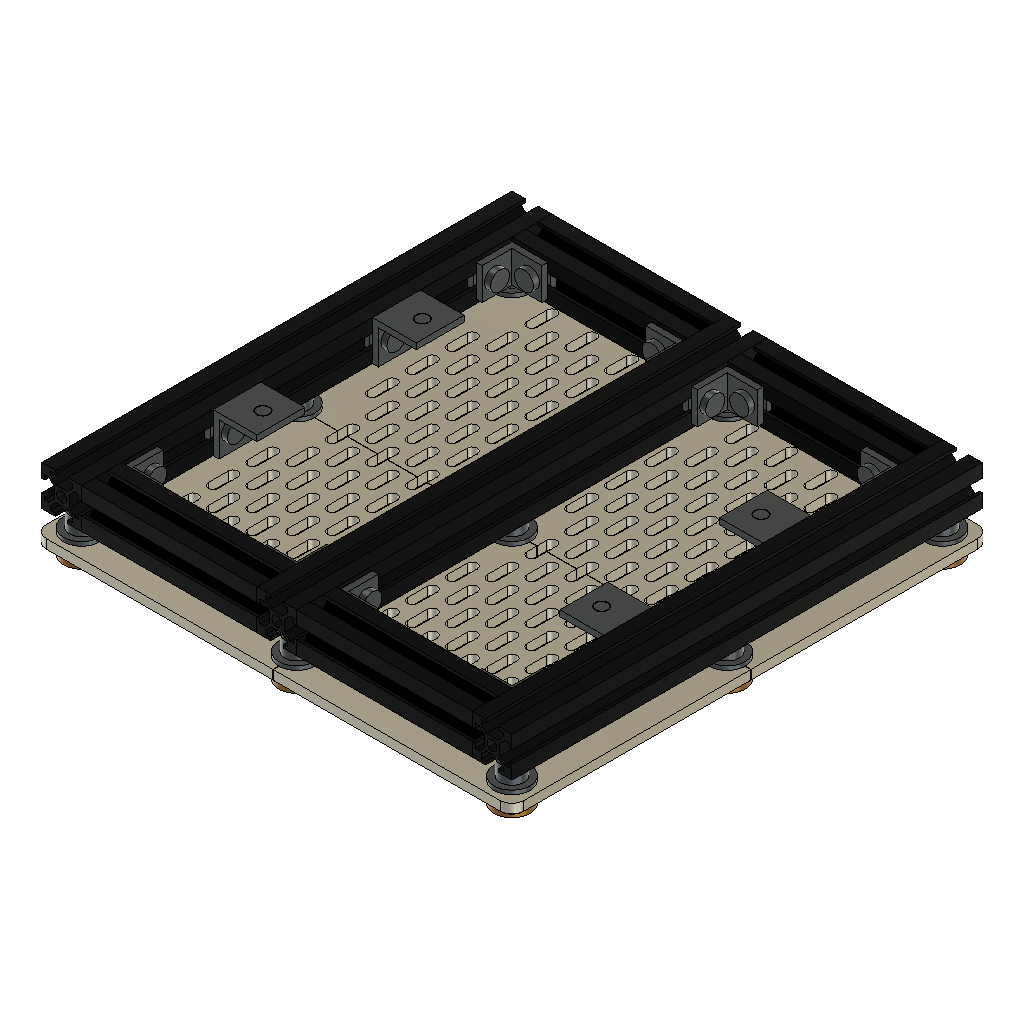
frame-assembly-v03 (Autodesk Fusion 360 design; units mm, degrees)
part number: 2026-10-27-16-26-25-331
part number: 2026-10-27-16-26-25-834
part number: 2026-10-27-16-26-31-002
part number: 2026-10-27-16-26-43-557
part number: 2026-10-27-16-27-03-703
part number: 2026-10-27-16-31-45-844
part number: 2026-10-27-16-32-06-116
part number: 2026-10-27-16-32-29-126
part number: 2026-10-27-16-32-54-655
part number: 2026-10-27-16-33-23-056
part number: 2026-10-27-16-33-54-185
part number: 2026-10-27-16-34-28-220
part number: 2026-10-27-16-50-17-475
part number: 2026-10-27-16-50-20-825
part number: 2026-10-27-16-50-30-983
part number: 2026-10-27-16-50-35-846
part number: 2026-10-27-16-50-39-540
part number: 2026-10-27-16-50-48-951
part number: 2026-10-27-16-50-52-817
part number: 2026-10-27-16-51-04-303
part number: 2026-10-27-16-51-09-754
part number: 2026-10-27-16-51-14-010
part number: 2026-10-27-16-51-20-182
part number: 2026-10-27-16-51-24-601
part number: 2026-10-27-16-51-37-683
part number: 2026-10-27-16-51-43-962
part number: 2026-10-27-16-51-48-789
part number: 2026-10-27-16-51-55-690
part number: 2026-10-27-16-52-00-678
part number: 2026-10-27-16-52-15-396
part number: 2026-10-27-16-52-22-451
part number: 2026-10-27-16-52-27-802
part number: 2026-10-27-16-52-35-541
part number: 2026-10-27-16-52-41-572
part number: 2026-10-27-16-52-57-940
part number: 2026-10-27-16-53-05-661
part number: 2026-10-27-16-53-11-607
part number: 2026-10-27-16-53-30-566
part number: 2026-10-27-16-53-36-573
part number: 2026-10-27-16-53-54-171
part number: 2026-10-27-16-54-02-574
part number: 2026-10-27-16-54-08-987
part number: 2026-10-27-16-54-18-294
part number: 2026-10-27-16-54-24-887
part number: 2026-10-27-16-54-44-208
part number: 2026-10-27-16-54-53-574
part number: 2026-10-27-16-55-00-850
part number: 2026-10-27-16-55-11-193
part number: 2026-10-27-16-55-18-638
part number: 2026-10-27-16-55-40-176
part number: 2026-10-27-16-55-50-211
part number: 2026-10-27-16-55-57-944
part number: 2026-10-27-16-56-09-225
part number: 2026-10-27-16-56-17-698
part number: 2026-10-27-16-56-42-856
part number: 2026-10-27-16-56-54-020
part number: 2026-10-27-16-57-02-669
part number: 2026-10-27-16-57-38-922
part number: 2026-10-27-16-58-05-764
part number: 2026-10-27-16-58-18-225
part number: 2026-10-27-16-58-32-485
part number: 2026-10-27-16-58-45-089
part number: 2026-10-27-16-59-01-629
part number: 2026-10-27-16-59-30-085
part number: 2026-10-27-16-59-42-842
part number: 2026-10-27-16-59-57-737
part number: 2026-10-27-17-00-10-688
part number: 2026-10-27-17-00-34-215
part number: 2026-10-27-17-01-04-234
part number: 2026-10-27-17-01-17-714
part number: 2026-10-27-17-01-33-549
part number: 2026-10-27-17-01-47-217
part number: 2026-10-27-17-02-03-116
part number: 2026-10-27-17-02-34-830
part number: 2026-10-27-17-02-49-172
part number: 2026-10-27-17-03-05-831
part number: 2026-10-27-17-03-20-448
part number: 2026-10-27-17-04-26-782
part number: 2026-10-27-17-05-00-628
part number: 2026-10-27-17-05-15-608
part number: 2026-10-27-17-05-33-129
part number: 2026-10-27-17-05-48-959
part number: 2026-10-27-17-06-06-857
part number: 2026-10-27-17-06-42-303
part number: 2026-10-27-17-06-58-375
part number: 2026-10-27-17-07-16-885
part number: 2026-10-27-17-07-33-101
part number: 2026-10-27-17-07-52-230
part number: 2026-10-27-17-08-29-249
part number: 2026-10-27-17-08-46-003
part number: 2026-10-27-17-09-05-462
part number: 2026-10-27-17-09-22-396
part number: 2026-10-27-17-09-42-184
part number: 2026-10-27-17-10-21-471
part number: 2026-10-27-17-10-38-969
part number: 2026-10-27-17-10-59-407
part number: 2026-10-27-17-11-17-340
part number: 2026-10-27-17-11-39-314
part number: 2026-10-27-17-12-12-457
part number: 2026-10-27-17-12-31-147
part number: 2026-10-27-17-13-02-003
part number: 2026-10-27-17-13-21-406
part number: 2026-10-27-17-13-50-114
part number: 2026-10-27-17-14-04-208
part number: 2026-10-27-17-14-39-027
part number: 2026-10-27-17-14-58-920
part number: 2026-10-27-17-15-33-071
part number: 2026-10-27-17-15-53-097
part number: 2026-10-27-17-16-23-156
part number: 2026-10-27-17-16-38-033
part number: 2026-10-27-17-17-14-342
part number: 2026-10-27-17-17-34-865
part number: 2026-10-27-17-18-08-534
part number: 2026-10-27-17-18-29-482
part number: 2026-10-27-17-19-04-183
part number: 2026-10-27-17-19-22-590
part number: 2026-10-27-17-20-03-829
part number: 2026-10-27-17-20-26-353
part number: 2026-10-27-17-21-03-350
part number: 2026-10-27-17-21-26-206
part number: 2026-10-27-17-22-00-497
Autodesk Fusion 360 part; units mm, degrees
(part 1 of 10)
sketch "01 Panel blank sketch" plane through (0, 0, 0) normal (0, 0, 1) x (1, 0, 0) in component "Panel lower left"
  line L0 (0.1, 0.1) -> (119.9, 0.1)
  line L1 (119.9, 0.1) -> (119.9, 119.9)
  line L2 (119.9, 119.9) -> (0.1, 119.9)
  line L3 (0.1, 119.9) -> (0.1, 0.1)
  dimension "d57" = 0.1
  dimension "d58" = 0.1
  dimension "d59" = 119.8
  dimension "d60" = 119.8
  constraint horizontal L0
  constraint vertical L1
  constraint horizontal L2
  constraint vertical L3
  measures "d57" horizontal distance of origin L0.start
  measures "d58" vertical distance of origin L0.start
  measures "d59" horizontal distance of L0.start L0.end
  measures "d60" vertical distance of L0.end L1.end
extrude "01 Panel blank" add sketch "01 Panel blank sketch" along normal blind 5 makes body 1 in component "Panel lower left"
fillet "02 Rounded exterior corners" radius 6 1 edges at (0.1, 0.1, 2.5) on bodies 1 in component "Panel lower left"
sketch "03 A main constrained seed" plane through (0, 0, 0) normal (0, 0, 1) x (1, 0, 0) in component "Panel lower left"
  line L0 (47.5, 25) -> (47.5, 35)
  arc A0 (47.5, 35) -> (42.5, 35) centre (45, 35) ccw
  line L1 (42.5, 35) -> (42.5, 25)
  arc A1 (42.5, 25) -> (47.5, 25) centre (45, 25) ccw
  line L2 (45, 25) -> (45, 35) construction
  line L3 (45, 25) -> (55, 25) construction
  dimension "d65" = 5
  dimension "d66" = 10
  dimension "d67" = 90
  dimension "d68" = 10
  dimension "d69" = 45
  dimension "d70" = 25
  constraint tangent L0 A0
  constraint tangent A0 L1
  constraint tangent L1 A1
  constraint tangent L0 A1
  constraint parallel L0 L1
  constraint horizontal L3
  measures "d65" diameter of A0
  measures "d66" distance of A1.centre A0.centre
  measures "d67" angle of L2 L3
  measures "d68" horizontal distance of A1.centre L3.end
  measures "d69" horizontal distance of origin A1.centre
  measures "d70" vertical distance of origin A1.centre
extrude "03 A main through cut" cut sketch "03 A main constrained seed" along normal blind 5 bodies 1 in component "Panel lower left"
pattern_linear "03 A main lattice" count 4 spacing 20 along (1, 0, 0) count 5 spacing 20 along (0, 1, 0) of "03 A main through cut" in component "Panel lower left"
sketch "04 A end strip constrained seed" plane through (0, 0, 0) normal (0, 0, 1) x (1, 0, 0) in component "Panel lower left"
  line L0 (27.5, 45) -> (27.5, 55)
  arc A0 (27.5, 55) -> (22.5, 55) centre (25, 55) ccw
  line L1 (22.5, 55) -> (22.5, 45)
  arc A1 (22.5, 45) -> (27.5, 45) centre (25, 45) ccw
  line L2 (25, 45) -> (25, 55) construction
  line L3 (25, 45) -> (35, 45) construction
  dimension "d77" = 5
  dimension "d78" = 10
  dimension "d79" = 90
  dimension "d80" = 10
  dimension "d81" = 25
  dimension "d82" = 45
  constraint tangent L0 A0
  constraint tangent A0 L1
  constraint tangent L1 A1
  constraint tangent L0 A1
  constraint parallel L0 L1
  constraint horizontal L3
  measures "d77" diameter of A0
  measures "d78" distance of A1.centre A0.centre
  measures "d79" angle of L2 L3
  measures "d80" horizontal distance of A1.centre L3.end
  measures "d81" horizontal distance of origin A1.centre
  measures "d82" vertical distance of origin A1.centre
extrude "04 A end strip through cut" cut sketch "04 A end strip constrained seed" along normal blind 5 bodies 1 in component "Panel lower left"
pattern_linear "04 A end strip lattice" count 1 spacing 20 along (1, 0, 0) count 3 spacing 20 along (0, 1, 0) of "04 A end strip through cut" in component "Panel lower left"
sketch "05 B main constrained seed" plane through (0, 0, 0) normal (0, 0, 1) x (1, 0, 0) in component "Panel lower left"
  line L0 (37.5, 15) -> (37.5, 25)
  arc A0 (37.5, 25) -> (32.5, 25) centre (35, 25) ccw
  line L1 (32.5, 25) -> (32.5, 15)
  arc A1 (32.5, 15) -> (37.5, 15) centre (35, 15) ccw
  line L2 (35, 15) -> (35, 25) construction
  line L3 (35, 15) -> (45, 15) construction
  dimension "d89" = 5
  dimension "d90" = 10
  dimension "d91" = 90
  dimension "d92" = 10
  dimension "d93" = 35
  dimension "d94" = 15
  constraint tangent L0 A0
  constraint tangent A0 L1
  constraint tangent L1 A1
  constraint tangent L0 A1
  constraint parallel L0 L1
  constraint horizontal L3
  measures "d89" diameter of A0
  measures "d90" distance of A1.centre A0.centre
  measures "d91" angle of L2 L3
  measures "d92" horizontal distance of A1.centre L3.end
  measures "d93" horizontal distance of origin A1.centre
  measures "d94" vertical distance of origin A1.centre
extrude "05 B main through cut" cut sketch "05 B main constrained seed" along normal blind 5 bodies 1 in component "Panel lower left"
pattern_linear "05 B main lattice" count 4 spacing 20 along (1, 0, 0) count 6 spacing 20 along (0, 1, 0) of "05 B main through cut" in component "Panel lower left"
sketch "06 B end strip constrained seed" plane through (0, 0, 0) normal (0, 0, 1) x (1, 0, 0) in component "Panel lower left"
  line L0 (117.5, 35) -> (117.5, 45)
  arc A0 (117.5, 45) -> (112.5, 45) centre (115, 45) ccw
  line L1 (112.5, 45) -> (112.5, 35)
  arc A1 (112.5, 35) -> (117.5, 35) centre (115, 35) ccw
  line L2 (115, 35) -> (115, 45) construction
  line L3 (115, 35) -> (125, 35) construction
  dimension "d101" = 5
  dimension "d102" = 10
  dimension "d103" = 90
  dimension "d104" = 10
  dimension "d105" = 115
  dimension "d106" = 35
  constraint tangent L0 A0
  constraint tangent A0 L1
  constraint tangent L1 A1
  constraint tangent L0 A1
  constraint parallel L0 L1
  constraint horizontal L3
  measures "d101" diameter of A0
  measures "d102" distance of A1.centre A0.centre
  measures "d103" angle of L2 L3
  measures "d104" horizontal distance of A1.centre L3.end
  measures "d105" horizontal distance of origin A1.centre
  measures "d106" vertical distance of origin A1.centre
extrude "06 B end strip through cut" cut sketch "06 B end strip constrained seed" along normal blind 5 bodies 1 in component "Panel lower left"
pattern_linear "06 B end strip lattice" count 1 spacing 20 along (1, 0, 0) count 4 spacing 20 along (0, 1, 0) of "06 B end strip through cut" in component "Panel lower left"
sketch "07 Shared node clearance sketch" plane through (0, 0, 0) normal (0, 0, 1) x (1, 0, 0) in component "Panel lower left"
  circle A0 centre (12, 12) radius 4.2
  dimension "d113" = 12
  dimension "d114" = 12
  dimension "d115" = 8.4
  measures "d113" horizontal distance of origin A0.centre
  measures "d114" vertical distance of origin A0.centre
  measures "d115" diameter of A0
extrude "07 Shared node clearance" cut sketch "07 Shared node clearance sketch" along normal blind 5 bodies 1 in component "Panel lower left"
sketch "07 Shared node clearance sketch (1)" plane through (0, 0, 0) normal (0, 0, 1) x (1, 0, 0) in component "Panel lower left"
  circle A0 centre (12, 120) radius 4.2
  dimension "d118" = 12
  dimension "d119" = 120
  dimension "d120" = 8.4
  measures "d118" horizontal distance of origin A0.centre
  measures "d119" vertical distance of origin A0.centre
  measures "d120" diameter of A0
extrude "07 Shared node clearance (1)" cut sketch "07 Shared node clearance sketch (1)" along normal blind 5 bodies 1 in component "Panel lower left"
sketch "07 Shared node clearance sketch (2)" plane through (0, 0, 0) normal (0, 0, 1) x (1, 0, 0) in component "Panel lower left"
  circle A0 centre (120, 12) radius 4.2
  dimension "d123" = 120
  dimension "d124" = 12
  dimension "d125" = 8.4
  measures "d123" horizontal distance of origin A0.centre
  measures "d124" vertical distance of origin A0.centre
  measures "d125" diameter of A0
extrude "07 Shared node clearance (2)" cut sketch "07 Shared node clearance sketch (2)" along normal blind 5 bodies 1 in component "Panel lower left"
sketch "07 Shared node clearance sketch (3)" plane through (0, 0, 0) normal (0, 0, 1) x (1, 0, 0) in component "Panel lower left"
  circle A0 centre (120, 120) radius 4.2
  dimension "d128" = 120
  dimension "d129" = 120
  dimension "d130" = 8.4
  measures "d128" horizontal distance of origin A0.centre
  measures "d129" vertical distance of origin A0.centre
  measures "d130" diameter of A0
extrude "07 Shared node clearance (3)" cut sketch "07 Shared node clearance sketch (3)" along normal blind 5 bodies 1 in component "Panel lower left"
fillet "08 Rounded slot entrances and face edges" radius 0.4 2 faces at (7.5667, 63.6667, 0) (7.5667, 63.6667, 0) on bodies 1 in component "Panel lower left"
ref_plane "WorkPlane1" through (0, 0, 5) normal (0, 0, 1) x (1, 0, 0) in component "Panel lower left"
sketch "09 Blind rear key socket sketch" plane through (0, 0, 5) normal (0, 0, 1) x (1, 0, 0) in component "Panel lower left"
  circle A0 centre (115, 70) radius 1.7
  dimension "d137" = 115
  dimension "d138" = 70
  dimension "d139" = 3.4
  measures "d137" horizontal distance of origin A0.centre
  measures "d138" vertical distance of origin A0.centre
  measures "d139" diameter of A0
ref_plane "WorkPlane2" through (0, 0, 5) normal (0, 0, 1) x (1, 0, 0) in component "Panel lower left"
sketch "09 Blind rear key socket sketch (1)" plane through (0, 0, 5) normal (0, 0, 1) x (1, 0, 0) in component "Panel lower left"
  circle A0 centre (70, 115) radius 1.7
  dimension "d144" = 70
  dimension "d145" = 115
  dimension "d146" = 3.4
  measures "d144" horizontal distance of origin A0.centre
  measures "d145" vertical distance of origin A0.centre
  measures "d146" diameter of A0
ref_plane "WorkPlane3" through (0, 0, 5) normal (0, 0, 1) x (1, 0, 0) in component "Panel lower left"
sketch "10 Node register socket sketch" plane through (0, 0, 5) normal (0, 0, 1) x (1, 0, 0) in component "Panel lower left"
  circle A0 centre (7, 7) radius 1.2
  dimension "d151" = 7
  dimension "d152" = 7
  dimension "d153" = 2.4
  measures "d151" horizontal distance of origin A0.centre
  measures "d152" vertical distance of origin A0.centre
  measures "d153" diameter of A0
extrude "10 Node register socket" cut sketch "10 Node register socket sketch" against normal blind 1 bodies 1 in component "Panel lower left"
ref_plane "WorkPlane4" through (0, 0, 5) normal (0, 0, 1) x (1, 0, 0) in component "Panel lower left"
sketch "10 Node register socket sketch (1)" plane through (0, 0, 5) normal (0, 0, 1) x (1, 0, 0) in component "Panel lower left"
  circle A0 centre (7, 17) radius 1.2
  dimension "d158" = 7
  dimension "d159" = 17
  dimension "d160" = 2.4
  measures "d158" horizontal distance of origin A0.centre
  measures "d159" vertical distance of origin A0.centre
  measures "d160" diameter of A0
extrude "10 Node register socket (1)" cut sketch "10 Node register socket sketch (1)" against normal blind 1 bodies 1 in component "Panel lower left"
ref_plane "WorkPlane5" through (0, 0, 5) normal (0, 0, 1) x (1, 0, 0) in component "Panel lower left"
sketch "10 Node register socket sketch (2)" plane through (0, 0, 5) normal (0, 0, 1) x (1, 0, 0) in component "Panel lower left"
  circle A0 centre (17, 7) radius 1.2
  dimension "d165" = 17
  dimension "d166" = 7
  dimension "d167" = 2.4
  measures "d165" horizontal distance of origin A0.centre
  measures "d166" vertical distance of origin A0.centre
  measures "d167" diameter of A0
extrude "10 Node register socket (2)" cut sketch "10 Node register socket sketch (2)" against normal blind 1 bodies 1 in component "Panel lower left"
ref_plane "WorkPlane6" through (0, 0, 5) normal (0, 0, 1) x (1, 0, 0) in component "Panel lower left"
sketch "10 Node register socket sketch (3)" plane through (0, 0, 5) normal (0, 0, 1) x (1, 0, 0) in component "Panel lower left"
  circle A0 centre (17, 17) radius 1.2
  dimension "d172" = 17
  dimension "d173" = 17
  dimension "d174" = 2.4
  measures "d172" horizontal distance of origin A0.centre
  measures "d173" vertical distance of origin A0.centre
  measures "d174" diameter of A0
extrude "10 Node register socket (3)" cut sketch "10 Node register socket sketch (3)" against normal blind 1 bodies 1 in component "Panel lower left"
ref_plane "WorkPlane7" through (0, 0, 5) normal (0, 0, 1) x (1, 0, 0) in component "Panel lower left"
sketch "10 Node register socket sketch (4)" plane through (0, 0, 5) normal (0, 0, 1) x (1, 0, 0) in component "Panel lower left"
  circle A0 centre (7, 115) radius 1.2
  dimension "d179" = 7
  dimension "d180" = 115
  dimension "d181" = 2.4
  measures "d179" horizontal distance of origin A0.centre
  measures "d180" vertical distance of origin A0.centre
  measures "d181" diameter of A0
extrude "10 Node register socket (4)" cut sketch "10 Node register socket sketch (4)" against normal blind 1 bodies 1 in component "Panel lower left"
ref_plane "WorkPlane8" through (0, 0, 5) normal (0, 0, 1) x (1, 0, 0) in component "Panel lower left"
sketch "10 Node register socket sketch (5)" plane through (0, 0, 5) normal (0, 0, 1) x (1, 0, 0) in component "Panel lower left"
  circle A0 centre (17, 115) radius 1.2
  dimension "d186" = 17
  dimension "d187" = 115
  dimension "d188" = 2.4
  measures "d186" horizontal distance of origin A0.centre
  measures "d187" vertical distance of origin A0.centre
  measures "d188" diameter of A0
extrude "10 Node register socket (5)" cut sketch "10 Node register socket sketch (5)" against normal blind 1 bodies 1 in component "Panel lower left"
ref_plane "WorkPlane9" through (0, 0, 5) normal (0, 0, 1) x (1, 0, 0) in component "Panel lower left"
sketch "10 Node register socket sketch (6)" plane through (0, 0, 5) normal (0, 0, 1) x (1, 0, 0) in component "Panel lower left"
  circle A0 centre (115, 7) radius 1.2
  dimension "d193" = 115
  dimension "d194" = 7
  dimension "d195" = 2.4
  measures "d193" horizontal distance of origin A0.centre
  measures "d194" vertical distance of origin A0.centre
  measures "d195" diameter of A0
extrude "10 Node register socket (6)" cut sketch "10 Node register socket sketch (6)" against normal blind 1 bodies 1 in component "Panel lower left"
ref_plane "WorkPlane10" through (0, 0, 5) normal (0, 0, 1) x (1, 0, 0) in component "Panel lower left"
sketch "10 Node register socket sketch (7)" plane through (0, 0, 5) normal (0, 0, 1) x (1, 0, 0) in component "Panel lower left"
  circle A0 centre (115, 17) radius 1.2
  dimension "d200" = 115
  dimension "d201" = 17
  dimension "d202" = 2.4
  measures "d200" horizontal distance of origin A0.centre
  measures "d201" vertical distance of origin A0.centre
  measures "d202" diameter of A0
extrude "10 Node register socket (7)" cut sketch "10 Node register socket sketch (7)" against normal blind 1 bodies 1 in component "Panel lower left"
ref_plane "WorkPlane11" through (0, 0, 5) normal (0, 0, 1) x (1, 0, 0) in component "Panel lower left"
sketch "10 Node register socket sketch (8)" plane through (0, 0, 5) normal (0, 0, 1) x (1, 0, 0) in component "Panel lower left"
  circle A0 centre (115, 115) radius 1.2
  dimension "d207" = 115
  dimension "d208" = 115
  dimension "d209" = 2.4
  measures "d207" horizontal distance of origin A0.centre
  measures "d208" vertical distance of origin A0.centre
  measures "d209" diameter of A0
extrude "10 Node register socket (8)" cut sketch "10 Node register socket sketch (8)" against normal blind 1 bodies 1 in component "Panel lower left"
sketch "01 Panel blank sketch (2)" plane through (0, 0, 0) normal (0, 0, 1) x (1, 0, 0) in component "Panel lower right"
  line L0 (120.1, 0.1) -> (239.9, 0.1)
  line L1 (239.9, 0.1) -> (239.9, 119.9)
  line L2 (239.9, 119.9) -> (120.1, 119.9)
  line L3 (120.1, 119.9) -> (120.1, 0.1)
  dimension "d216" = 120.1
  dimension "d217" = 0.1
  dimension "d218" = 119.8
  dimension "d219" = 119.8
  constraint horizontal L0
  constraint vertical L1
  constraint horizontal L2
  constraint vertical L3
  measures "d216" horizontal distance of origin L0.start
  measures "d217" vertical distance of origin L0.start
  measures "d218" horizontal distance of L0.start L0.end
  measures "d219" vertical distance of L0.end L1.end
extrude "01 Panel blank'" add sketch "01 Panel blank sketch (2)" along normal blind 5 separate body makes body 2 in component "Panel lower right"
fillet "02 Rounded exterior corners'" radius 6 1 edges at (239.9, 0.1, 2.5) on bodies 2 in component "Panel lower right"
sketch "03 A main constrained seed (2)" plane through (0, 0, 0) normal (0, 0, 1) x (1, 0, 0) in component "Panel lower right"
  line L0 (147.5, 25) -> (147.5, 35)
  arc A0 (147.5, 35) -> (142.5, 35) centre (145, 35) ccw
  line L1 (142.5, 35) -> (142.5, 25)
  arc A1 (142.5, 25) -> (147.5, 25) centre (145, 25) ccw
  line L2 (145, 25) -> (145, 35) construction
  line L3 (145, 25) -> (155, 25) construction
  dimension "d224" = 5
  dimension "d225" = 10
  dimension "d226" = 90
  dimension "d227" = 10
  dimension "d228" = 145
  dimension "d229" = 25
  constraint tangent L0 A0
  constraint tangent A0 L1
  constraint tangent L1 A1
  constraint tangent L0 A1
  constraint parallel L0 L1
  constraint horizontal L3
  measures "d224" diameter of A0
  measures "d225" distance of A1.centre A0.centre
  measures "d226" angle of L2 L3
  measures "d227" horizontal distance of A1.centre L3.end
  measures "d228" horizontal distance of origin A1.centre
  measures "d229" vertical distance of origin A1.centre
extrude "03 A main through cut'" cut sketch "03 A main constrained seed (2)" along normal blind 5 bodies 2 in component "Panel lower right"
pattern_linear "03 A main lattice'" count 4 spacing 20 along (1, 0, 0) count 5 spacing 20 along (0, 1, 0) of "03 A main through cut'" in component "Panel lower right"
sketch "04 A end strip constrained seed (2)" plane through (0, 0, 0) normal (0, 0, 1) x (1, 0, 0) in component "Panel lower right"
  line L0 (127.5, 45) -> (127.5, 55)
  arc A0 (127.5, 55) -> (122.5, 55) centre (125, 55) ccw
  line L1 (122.5, 55) -> (122.5, 45)
  arc A1 (122.5, 45) -> (127.5, 45) centre (125, 45) ccw
  line L2 (125, 45) -> (125, 55) construction
  line L3 (125, 45) -> (135, 45) construction
  dimension "d236" = 5
  dimension "d237" = 10
  dimension "d238" = 90
  dimension "d239" = 10
  dimension "d240" = 125
  dimension "d241" = 45
  constraint tangent L0 A0
  constraint tangent A0 L1
  constraint tangent L1 A1
  constraint tangent L0 A1
  constraint parallel L0 L1
  constraint horizontal L3
  measures "d236" diameter of A0
  measures "d237" distance of A1.centre A0.centre
  measures "d238" angle of L2 L3
  measures "d239" horizontal distance of A1.centre L3.end
  measures "d240" horizontal distance of origin A1.centre
  measures "d241" vertical distance of origin A1.centre
extrude "04 A end strip through cut'" cut sketch "04 A end strip constrained seed (2)" along normal blind 5 bodies 2 in component "Panel lower right"
pattern_linear "04 A end strip lattice'" count 1 spacing 20 along (1, 0, 0) count 3 spacing 20 along (0, 1, 0) of "04 A end strip through cut'" in component "Panel lower right"
sketch "05 B main constrained seed (2)" plane through (0, 0, 0) normal (0, 0, 1) x (1, 0, 0) in component "Panel lower right"
  line L0 (137.5, 15) -> (137.5, 25)
  arc A0 (137.5, 25) -> (132.5, 25) centre (135, 25) ccw
  line L1 (132.5, 25) -> (132.5, 15)
  arc A1 (132.5, 15) -> (137.5, 15) centre (135, 15) ccw
  line L2 (135, 15) -> (135, 25) construction
  line L3 (135, 15) -> (145, 15) construction
  dimension "d248" = 5
  dimension "d249" = 10
  dimension "d250" = 90
  dimension "d251" = 10
  dimension "d252" = 135
  dimension "d253" = 15
  constraint tangent L0 A0
  constraint tangent A0 L1
  constraint tangent L1 A1
  constraint tangent L0 A1
  constraint parallel L0 L1
  constraint horizontal L3
  measures "d248" diameter of A0
  measures "d249" distance of A1.centre A0.centre
  measures "d250" angle of L2 L3
  measures "d251" horizontal distance of A1.centre L3.end
  measures "d252" horizontal distance of origin A1.centre
  measures "d253" vertical distance of origin A1.centre
extrude "05 B main through cut'" cut sketch "05 B main constrained seed (2)" along normal blind 5 bodies 2 in component "Panel lower right"
pattern_linear "05 B main lattice'" count 4 spacing 20 along (1, 0, 0) count 6 spacing 20 along (0, 1, 0) of "05 B main through cut'" in component "Panel lower right"
sketch "06 B end strip constrained seed (2)" plane through (0, 0, 0) normal (0, 0, 1) x (1, 0, 0) in component "Panel lower right"
  line L0 (217.5, 35) -> (217.5, 45)
  arc A0 (217.5, 45) -> (212.5, 45) centre (215, 45) ccw
  line L1 (212.5, 45) -> (212.5, 35)
  arc A1 (212.5, 35) -> (217.5, 35) centre (215, 35) ccw
  line L2 (215, 35) -> (215, 45) construction
  line L3 (215, 35) -> (225, 35) construction
  dimension "d260" = 5
  dimension "d261" = 10
  dimension "d262" = 90
  dimension "d263" = 10
  dimension "d264" = 215
  dimension "d265" = 35
  constraint tangent L0 A0
  constraint tangent A0 L1
  constraint tangent L1 A1
  constraint tangent L0 A1
  constraint parallel L0 L1
  constraint horizontal L3
  measures "d260" diameter of A0
  measures "d261" distance of A1.centre A0.centre
  measures "d262" angle of L2 L3
  measures "d263" horizontal distance of A1.centre L3.end
  measures "d264" horizontal distance of origin A1.centre
  measures "d265" vertical distance of origin A1.centre
extrude "06 B end strip through cut'" cut sketch "06 B end strip constrained seed (2)" along normal blind 5 bodies 2 in component "Panel lower right"
pattern_linear "06 B end strip lattice'" count 1 spacing 20 along (1, 0, 0) count 4 spacing 20 along (0, 1, 0) of "06 B end strip through cut'" in component "Panel lower right"
sketch "07 Shared node clearance sketch (4)" plane through (0, 0, 0) normal (0, 0, 1) x (1, 0, 0) in component "Panel lower right"
  circle A0 centre (120, 12) radius 4.2
  dimension "d272" = 120
  dimension "d273" = 12
  dimension "d274" = 8.4
  measures "d272" horizontal distance of origin A0.centre
  measures "d273" vertical distance of origin A0.centre
  measures "d274" diameter of A0
extrude "07 Shared node clearance'" cut sketch "07 Shared node clearance sketch (4)" along normal blind 5 bodies 2 in component "Panel lower right"
sketch "07 Shared node clearance sketch (1) (2)" plane through (0, 0, 0) normal (0, 0, 1) x (1, 0, 0) in component "Panel lower right"
  circle A0 centre (120, 120) radius 4.2
  dimension "d277" = 120
  dimension "d278" = 120
  dimension "d279" = 8.4
  measures "d277" horizontal distance of origin A0.centre
  measures "d278" vertical distance of origin A0.centre
  measures "d279" diameter of A0
extrude "07 Shared node clearance (1)'" cut sketch "07 Shared node clearance sketch (1) (2)" along normal blind 5 bodies 2 in component "Panel lower right"
sketch "07 Shared node clearance sketch (2) (2)" plane through (0, 0, 0) normal (0, 0, 1) x (1, 0, 0) in component "Panel lower right"
  circle A0 centre (228, 12) radius 4.2
  dimension "d282" = 228
  dimension "d283" = 12
  dimension "d284" = 8.4
  measures "d282" horizontal distance of origin A0.centre
  measures "d283" vertical distance of origin A0.centre
  measures "d284" diameter of A0
extrude "07 Shared node clearance (2)'" cut sketch "07 Shared node clearance sketch (2) (2)" along normal blind 5 bodies 2 in component "Panel lower right"
sketch "07 Shared node clearance sketch (3) (2)" plane through (0, 0, 0) normal (0, 0, 1) x (1, 0, 0) in component "Panel lower right"
  circle A0 centre (228, 120) radius 4.2
  dimension "d287" = 228
  dimension "d288" = 120
  dimension "d289" = 8.4
  measures "d287" horizontal distance of origin A0.centre
  measures "d288" vertical distance of origin A0.centre
  measures "d289" diameter of A0
extrude "07 Shared node clearance (3)'" cut sketch "07 Shared node clearance sketch (3) (2)" along normal blind 5 bodies 2 in component "Panel lower right"
fillet "08 Rounded slot entrances and face edges'" radius 0.4 2 faces at (232.4333, 63.6667, 0) (232.4333, 63.6667, 0) on bodies 2 in component "Panel lower right"
ref_plane "WorkPlane1" through (0, 0, 5) normal (0, 0, 1) x (1, 0, 0) in component "Panel lower right"
sketch "09 Blind rear key socket sketch (2)" plane through (0, 0, 5) normal (0, 0, 1) x (1, 0, 0) in component "Panel lower right"
  circle A0 centre (125, 80) radius 1.7
  dimension "d296" = 125
  dimension "d297" = 80
  dimension "d298" = 3.4
  measures "d296" horizontal distance of origin A0.centre
  measures "d297" vertical distance of origin A0.centre
  measures "d298" diameter of A0
ref_plane "WorkPlane2" through (0, 0, 5) normal (0, 0, 1) x (1, 0, 0) in component "Panel lower right"
sketch "09 Blind rear key socket sketch (1) (2)" plane through (0, 0, 5) normal (0, 0, 1) x (1, 0, 0) in component "Panel lower right"
  circle A0 centre (190, 115) radius 1.7
  dimension "d303" = 190
  dimension "d304" = 115
  dimension "d305" = 3.4
  measures "d303" horizontal distance of origin A0.centre
  measures "d304" vertical distance of origin A0.centre
  measures "d305" diameter of A0
ref_plane "WorkPlane3" through (0, 0, 5) normal (0, 0, 1) x (1, 0, 0) in component "Panel lower right"
sketch "10 Node register socket sketch (9)" plane through (0, 0, 5) normal (0, 0, 1) x (1, 0, 0) in component "Panel lower right"
  circle A0 centre (125, 7) radius 1.2
  dimension "d310" = 125
  dimension "d311" = 7
  dimension "d312" = 2.4
  measures "d310" horizontal distance of origin A0.centre
  measures "d311" vertical distance of origin A0.centre
  measures "d312" diameter of A0
extrude "10 Node register socket'" cut sketch "10 Node register socket sketch (9)" against normal blind 1 bodies 2 in component "Panel lower right"
ref_plane "WorkPlane4" through (0, 0, 5) normal (0, 0, 1) x (1, 0, 0) in component "Panel lower right"
sketch "10 Node register socket sketch (1) (2)" plane through (0, 0, 5) normal (0, 0, 1) x (1, 0, 0) in component "Panel lower right"
  circle A0 centre (125, 17) radius 1.2
  dimension "d317" = 125
  dimension "d318" = 17
  dimension "d319" = 2.4
  measures "d317" horizontal distance of origin A0.centre
  measures "d318" vertical distance of origin A0.centre
  measures "d319" diameter of A0
extrude "10 Node register socket (1)'" cut sketch "10 Node register socket sketch (1) (2)" against normal blind 1 bodies 2 in component "Panel lower right"
ref_plane "WorkPlane5" through (0, 0, 5) normal (0, 0, 1) x (1, 0, 0) in component "Panel lower right"
sketch "10 Node register socket sketch (2) (2)" plane through (0, 0, 5) normal (0, 0, 1) x (1, 0, 0) in component "Panel lower right"
  circle A0 centre (125, 115) radius 1.2
  dimension "d324" = 125
  dimension "d325" = 115
  dimension "d326" = 2.4
  measures "d324" horizontal distance of origin A0.centre
  measures "d325" vertical distance of origin A0.centre
  measures "d326" diameter of A0
extrude "10 Node register socket (2)'" cut sketch "10 Node register socket sketch (2) (2)" against normal blind 1 bodies 2 in component "Panel lower right"
ref_plane "WorkPlane6" through (0, 0, 5) normal (0, 0, 1) x (1, 0, 0) in component "Panel lower right"
sketch "10 Node register socket sketch (3) (2)" plane through (0, 0, 5) normal (0, 0, 1) x (1, 0, 0) in component "Panel lower right"
  circle A0 centre (223, 7) radius 1.2
  dimension "d331" = 223
  dimension "d332" = 7
  dimension "d333" = 2.4
  measures "d331" horizontal distance of origin A0.centre
  measures "d332" vertical distance of origin A0.centre
  measures "d333" diameter of A0
extrude "10 Node register socket (3)'" cut sketch "10 Node register socket sketch (3) (2)" against normal blind 1 bodies 2 in component "Panel lower right"
ref_plane "WorkPlane7" through (0, 0, 5) normal (0, 0, 1) x (1, 0, 0) in component "Panel lower right"
sketch "10 Node register socket sketch (4) (2)" plane through (0, 0, 5) normal (0, 0, 1) x (1, 0, 0) in component "Panel lower right"
  circle A0 centre (223, 17) radius 1.2
  dimension "d338" = 223
  dimension "d339" = 17
  dimension "d340" = 2.4
  measures "d338" horizontal distance of origin A0.centre
  measures "d339" vertical distance of origin A0.centre
  measures "d340" diameter of A0
extrude "10 Node register socket (4)'" cut sketch "10 Node register socket sketch (4) (2)" against normal blind 1 bodies 2 in component "Panel lower right"
ref_plane "WorkPlane8" through (0, 0, 5) normal (0, 0, 1) x (1, 0, 0) in component "Panel lower right"
sketch "10 Node register socket sketch (5) (2)" plane through (0, 0, 5) normal (0, 0, 1) x (1, 0, 0) in component "Panel lower right"
  circle A0 centre (233, 7) radius 1.2
  dimension "d345" = 233
  dimension "d346" = 7
  dimension "d347" = 2.4
  measures "d345" horizontal distance of origin A0.centre
  measures "d346" vertical distance of origin A0.centre
  measures "d347" diameter of A0
extrude "10 Node register socket (5)'" cut sketch "10 Node register socket sketch (5) (2)" against normal blind 1 bodies 2 in component "Panel lower right"
ref_plane "WorkPlane9" through (0, 0, 5) normal (0, 0, 1) x (1, 0, 0) in component "Panel lower right"
sketch "10 Node register socket sketch (6) (2)" plane through (0, 0, 5) normal (0, 0, 1) x (1, 0, 0) in component "Panel lower right"
  circle A0 centre (233, 17) radius 1.2
  dimension "d352" = 233
  dimension "d353" = 17
  dimension "d354" = 2.4
  measures "d352" horizontal distance of origin A0.centre
  measures "d353" vertical distance of origin A0.centre
  measures "d354" diameter of A0
extrude "10 Node register socket (6)'" cut sketch "10 Node register socket sketch (6) (2)" against normal blind 1 bodies 2 in component "Panel lower right"
ref_plane "WorkPlane10" through (0, 0, 5) normal (0, 0, 1) x (1, 0, 0) in component "Panel lower right"
sketch "10 Node register socket sketch (7) (2)" plane through (0, 0, 5) normal (0, 0, 1) x (1, 0, 0) in component "Panel lower right"
  circle A0 centre (223, 115) radius 1.2
  dimension "d359" = 223
  dimension "d360" = 115
  dimension "d361" = 2.4
  measures "d359" horizontal distance of origin A0.centre
  measures "d360" vertical distance of origin A0.centre
  measures "d361" diameter of A0
extrude "10 Node register socket (7)'" cut sketch "10 Node register socket sketch (7) (2)" against normal blind 1 bodies 2 in component "Panel lower right"
ref_plane "WorkPlane11" through (0, 0, 5) normal (0, 0, 1) x (1, 0, 0) in component "Panel lower right"
sketch "10 Node register socket sketch (8) (2)" plane through (0, 0, 5) normal (0, 0, 1) x (1, 0, 0) in component "Panel lower right"
  circle A0 centre (233, 115) radius 1.2
  dimension "d366" = 233
  dimension "d367" = 115
  dimension "d368" = 2.4
  measures "d366" horizontal distance of origin A0.centre
  measures "d367" vertical distance of origin A0.centre
  measures "d368" diameter of A0
extrude "10 Node register socket (8)'" cut sketch "10 Node register socket sketch (8) (2)" against normal blind 1 bodies 2 in component "Panel lower right"
sketch "01 Panel blank sketch (3)" plane through (0, 0, 0) normal (0, 0, 1) x (1, 0, 0) in component "Panel upper left"
  line L0 (0.1, 120.1) -> (119.9, 120.1)
  line L1 (119.9, 120.1) -> (119.9, 239.9)
  line L2 (119.9, 239.9) -> (0.1, 239.9)
  line L3 (0.1, 239.9) -> (0.1, 120.1)
  dimension "d375" = 0.1
  dimension "d376" = 120.1
  dimension "d377" = 119.8
  dimension "d378" = 119.8
  constraint horizontal L0
  constraint vertical L1
  constraint horizontal L2
  constraint vertical L3
  measures "d375" horizontal distance of origin L0.start
  measures "d376" vertical distance of origin L0.start
  measures "d377" horizontal distance of L0.start L0.end
  measures "d378" vertical distance of L0.end L1.end
extrude "01 Panel blank''" add sketch "01 Panel blank sketch (3)" along normal blind 5 separate body makes body 3 in component "Panel upper left"
fillet "02 Rounded exterior corners''" radius 6 1 edges at (0.1, 239.9, 2.5) on bodies 3 in component "Panel upper left"
sketch "03 A main constrained seed (3)" plane through (0, 0, 0) normal (0, 0, 1) x (1, 0, 0) in component "Panel upper left"
  line L0 (47.5, 125) -> (47.5, 135)
  arc A0 (47.5, 135) -> (42.5, 135) centre (45, 135) ccw
  line L1 (42.5, 135) -> (42.5, 125)
  arc A1 (42.5, 125) -> (47.5, 125) centre (45, 125) ccw
  line L2 (45, 125) -> (45, 135) construction
  line L3 (45, 125) -> (55, 125) construction
  dimension "d383" = 5
  dimension "d384" = 10
  dimension "d385" = 90
  dimension "d386" = 10
  dimension "d387" = 45
  dimension "d388" = 125
  constraint tangent L0 A0
  constraint tangent A0 L1
  constraint tangent L1 A1
  constraint tangent L0 A1
  constraint parallel L0 L1
  constraint horizontal L3
  measures "d383" diameter of A0
  measures "d384" distance of A1.centre A0.centre
  measures "d385" angle of L2 L3
  measures "d386" horizontal distance of A1.centre L3.end
  measures "d387" horizontal distance of origin A1.centre
  measures "d388" vertical distance of origin A1.centre
extrude "03 A main through cut''" cut sketch "03 A main constrained seed (3)" along normal blind 5 bodies 3 in component "Panel upper left"
pattern_linear "03 A main lattice''" count 4 spacing 20 along (1, 0, 0) count 5 spacing 20 along (0, 1, 0) of "03 A main through cut''" in component "Panel upper left"
sketch "04 A end strip constrained seed (3)" plane through (0, 0, 0) normal (0, 0, 1) x (1, 0, 0) in component "Panel upper left"
  line L0 (27.5, 145) -> (27.5, 155)
  arc A0 (27.5, 155) -> (22.5, 155) centre (25, 155) ccw
  line L1 (22.5, 155) -> (22.5, 145)
  arc A1 (22.5, 145) -> (27.5, 145) centre (25, 145) ccw
  line L2 (25, 145) -> (25, 155) construction
  line L3 (25, 145) -> (35, 145) construction
  dimension "d395" = 5
  dimension "d396" = 10
  dimension "d397" = 90
  dimension "d398" = 10
  dimension "d399" = 25
  dimension "d400" = 145
  constraint tangent L0 A0
  constraint tangent A0 L1
  constraint tangent L1 A1
  constraint tangent L0 A1
  constraint parallel L0 L1
  constraint horizontal L3
  measures "d395" diameter of A0
  measures "d396" distance of A1.centre A0.centre
  measures "d397" angle of L2 L3
  measures "d398" horizontal distance of A1.centre L3.end
  measures "d399" horizontal distance of origin A1.centre
  measures "d400" vertical distance of origin A1.centre
extrude "04 A end strip through cut''" cut sketch "04 A end strip constrained seed (3)" along normal blind 5 bodies 3 in component "Panel upper left"
pattern_linear "04 A end strip lattice''" count 1 spacing 20 along (1, 0, 0) count 3 spacing 20 along (0, 1, 0) of "04 A end strip through cut''" in component "Panel upper left"
sketch "05 B main constrained seed (3)" plane through (0, 0, 0) normal (0, 0, 1) x (1, 0, 0) in component "Panel upper left"
  line L0 (37.5, 115) -> (37.5, 125)
  arc A0 (37.5, 125) -> (32.5, 125) centre (35, 125) ccw
  line L1 (32.5, 125) -> (32.5, 115)
  arc A1 (32.5, 115) -> (37.5, 115) centre (35, 115) ccw
  line L2 (35, 115) -> (35, 125) construction
  line L3 (35, 115) -> (45, 115) construction
  dimension "d407" = 5
  dimension "d408" = 10
  dimension "d409" = 90
  dimension "d410" = 10
  dimension "d411" = 35
  dimension "d412" = 115
  constraint tangent L0 A0
  constraint tangent A0 L1
  constraint tangent L1 A1
  constraint tangent L0 A1
  constraint parallel L0 L1
  constraint horizontal L3
  measures "d407" diameter of A0
  measures "d408" distance of A1.centre A0.centre
  measures "d409" angle of L2 L3
  measures "d410" horizontal distance of A1.centre L3.end
  measures "d411" horizontal distance of origin A1.centre
  measures "d412" vertical distance of origin A1.centre
extrude "05 B main through cut''" cut sketch "05 B main constrained seed (3)" along normal blind 5 bodies 3 in component "Panel upper left"
pattern_linear "05 B main lattice''" count 4 spacing 20 along (1, 0, 0) count 6 spacing 20 along (0, 1, 0) of "05 B main through cut''" in component "Panel upper left"
sketch "06 B end strip constrained seed (3)" plane through (0, 0, 0) normal (0, 0, 1) x (1, 0, 0) in component "Panel upper left"
  line L0 (117.5, 135) -> (117.5, 145)
  arc A0 (117.5, 145) -> (112.5, 145) centre (115, 145) ccw
  line L1 (112.5, 145) -> (112.5, 135)
  arc A1 (112.5, 135) -> (117.5, 135) centre (115, 135) ccw
  line L2 (115, 135) -> (115, 145) construction
  line L3 (115, 135) -> (125, 135) construction
  dimension "d419" = 5
  dimension "d420" = 10
  dimension "d421" = 90
  dimension "d422" = 10
  dimension "d423" = 115
  dimension "d424" = 135
  constraint tangent L0 A0
  constraint tangent A0 L1
  constraint tangent L1 A1
  constraint tangent L0 A1
  constraint parallel L0 L1
  constraint horizontal L3
  measures "d419" diameter of A0
  measures "d420" distance of A1.centre A0.centre
  measures "d421" angle of L2 L3
  measures "d422" horizontal distance of A1.centre L3.end
  measures "d423" horizontal distance of origin A1.centre
  measures "d424" vertical distance of origin A1.centre
extrude "06 B end strip through cut''" cut sketch "06 B end strip constrained seed (3)" along normal blind 5 bodies 3 in component "Panel upper left"
pattern_linear "06 B end strip lattice''" count 1 spacing 20 along (1, 0, 0) count 4 spacing 20 along (0, 1, 0) of "06 B end strip through cut''" in component "Panel upper left"
sketch "07 Shared node clearance sketch (5)" plane through (0, 0, 0) normal (0, 0, 1) x (1, 0, 0) in component "Panel upper left"
  circle A0 centre (12, 120) radius 4.2
  dimension "d431" = 12
  dimension "d432" = 120
  dimension "d433" = 8.4
  measures "d431" horizontal distance of origin A0.centre
  measures "d432" vertical distance of origin A0.centre
  measures "d433" diameter of A0
extrude "07 Shared node clearance''" cut sketch "07 Shared node clearance sketch (5)" along normal blind 5 bodies 3 in component "Panel upper left"
sketch "07 Shared node clearance sketch (1) (3)" plane through (0, 0, 0) normal (0, 0, 1) x (1, 0, 0) in component "Panel upper left"
  circle A0 centre (12, 228) radius 4.2
  dimension "d436" = 12
  dimension "d437" = 228
  dimension "d438" = 8.4
  measures "d436" horizontal distance of origin A0.centre
  measures "d437" vertical distance of origin A0.centre
  measures "d438" diameter of A0
extrude "07 Shared node clearance (1)''" cut sketch "07 Shared node clearance sketch (1) (3)" along normal blind 5 bodies 3 in component "Panel upper left"
sketch "07 Shared node clearance sketch (2) (3)" plane through (0, 0, 0) normal (0, 0, 1) x (1, 0, 0) in component "Panel upper left"
  circle A0 centre (120, 120) radius 4.2
  dimension "d441" = 120
  dimension "d442" = 120
  dimension "d443" = 8.4
  measures "d441" horizontal distance of origin A0.centre
  measures "d442" vertical distance of origin A0.centre
  measures "d443" diameter of A0
extrude "07 Shared node clearance (2)''" cut sketch "07 Shared node clearance sketch (2) (3)" along normal blind 5 bodies 3 in component "Panel upper left"
sketch "07 Shared node clearance sketch (3) (3)" plane through (0, 0, 0) normal (0, 0, 1) x (1, 0, 0) in component "Panel upper left"
  circle A0 centre (120, 228) radius 4.2
  dimension "d446" = 120
  dimension "d447" = 228
  dimension "d448" = 8.4
  measures "d446" horizontal distance of origin A0.centre
  measures "d447" vertical distance of origin A0.centre
  measures "d448" diameter of A0
extrude "07 Shared node clearance (3)''" cut sketch "07 Shared node clearance sketch (3) (3)" along normal blind 5 bodies 3 in component "Panel upper left"
fillet "08 Rounded slot entrances and face edges''" radius 0.4 2 faces at (7.5667, 176.3333, 0) (7.5667, 176.3333, 0) on bodies 3 in component "Panel upper left"
ref_plane "WorkPlane1" through (0, 0, 5) normal (0, 0, 1) x (1, 0, 0) in component "Panel upper left"
sketch "09 Blind rear key socket sketch (3)" plane through (0, 0, 5) normal (0, 0, 1) x (1, 0, 0) in component "Panel upper left"
  circle A0 centre (115, 190) radius 1.7
  dimension "d455" = 115
  dimension "d456" = 190
  dimension "d457" = 3.4
  measures "d455" horizontal distance of origin A0.centre
  measures "d456" vertical distance of origin A0.centre
  measures "d457" diameter of A0
ref_plane "WorkPlane2" through (0, 0, 5) normal (0, 0, 1) x (1, 0, 0) in component "Panel upper left"
sketch "09 Blind rear key socket sketch (1) (3)" plane through (0, 0, 5) normal (0, 0, 1) x (1, 0, 0) in component "Panel upper left"
  circle A0 centre (70, 125) radius 1.7
  dimension "d462" = 70
  dimension "d463" = 125
  dimension "d464" = 3.4
  measures "d462" horizontal distance of origin A0.centre
  measures "d463" vertical distance of origin A0.centre
  measures "d464" diameter of A0
ref_plane "WorkPlane3" through (0, 0, 5) normal (0, 0, 1) x (1, 0, 0) in component "Panel upper left"
sketch "10 Node register socket sketch (10)" plane through (0, 0, 5) normal (0, 0, 1) x (1, 0, 0) in component "Panel upper left"
  circle A0 centre (7, 125) radius 1.2
  dimension "d469" = 7
  dimension "d470" = 125
  dimension "d471" = 2.4
  measures "d469" horizontal distance of origin A0.centre
  measures "d470" vertical distance of origin A0.centre
  measures "d471" diameter of A0
extrude "10 Node register socket''" cut sketch "10 Node register socket sketch (10)" against normal blind 1 bodies 3 in component "Panel upper left"
ref_plane "WorkPlane4" through (0, 0, 5) normal (0, 0, 1) x (1, 0, 0) in component "Panel upper left"
sketch "10 Node register socket sketch (1) (3)" plane through (0, 0, 5) normal (0, 0, 1) x (1, 0, 0) in component "Panel upper left"
  circle A0 centre (17, 125) radius 1.2
  dimension "d476" = 17
  dimension "d477" = 125
  dimension "d478" = 2.4
  measures "d476" horizontal distance of origin A0.centre
  measures "d477" vertical distance of origin A0.centre
  measures "d478" diameter of A0
extrude "10 Node register socket (1)''" cut sketch "10 Node register socket sketch (1) (3)" against normal blind 1 bodies 3 in component "Panel upper left"
ref_plane "WorkPlane5" through (0, 0, 5) normal (0, 0, 1) x (1, 0, 0) in component "Panel upper left"
sketch "10 Node register socket sketch (2) (3)" plane through (0, 0, 5) normal (0, 0, 1) x (1, 0, 0) in component "Panel upper left"
  circle A0 centre (7, 223) radius 1.2
  dimension "d483" = 7
  dimension "d484" = 223
  dimension "d485" = 2.4
  measures "d483" horizontal distance of origin A0.centre
  measures "d484" vertical distance of origin A0.centre
  measures "d485" diameter of A0
extrude "10 Node register socket (2)''" cut sketch "10 Node register socket sketch (2) (3)" against normal blind 1 bodies 3 in component "Panel upper left"
ref_plane "WorkPlane6" through (0, 0, 5) normal (0, 0, 1) x (1, 0, 0) in component "Panel upper left"
sketch "10 Node register socket sketch (3) (3)" plane through (0, 0, 5) normal (0, 0, 1) x (1, 0, 0) in component "Panel upper left"
  circle A0 centre (7, 233) radius 1.2
  dimension "d490" = 7
  dimension "d491" = 233
  dimension "d492" = 2.4
  measures "d490" horizontal distance of origin A0.centre
  measures "d491" vertical distance of origin A0.centre
  measures "d492" diameter of A0
extrude "10 Node register socket (3)''" cut sketch "10 Node register socket sketch (3) (3)" against normal blind 1 bodies 3 in component "Panel upper left"
ref_plane "WorkPlane7" through (0, 0, 5) normal (0, 0, 1) x (1, 0, 0) in component "Panel upper left"
sketch "10 Node register socket sketch (4) (3)" plane through (0, 0, 5) normal (0, 0, 1) x (1, 0, 0) in component "Panel upper left"
  circle A0 centre (17, 223) radius 1.2
  dimension "d497" = 17
  dimension "d498" = 223
  dimension "d499" = 2.4
  measures "d497" horizontal distance of origin A0.centre
  measures "d498" vertical distance of origin A0.centre
  measures "d499" diameter of A0
extrude "10 Node register socket (4)''" cut sketch "10 Node register socket sketch (4) (3)" against normal blind 1 bodies 3 in component "Panel upper left"
ref_plane "WorkPlane8" through (0, 0, 5) normal (0, 0, 1) x (1, 0, 0) in component "Panel upper left"
sketch "10 Node register socket sketch (5) (3)" plane through (0, 0, 5) normal (0, 0, 1) x (1, 0, 0) in component "Panel upper left"
  circle A0 centre (17, 233) radius 1.2
  dimension "d504" = 17
  dimension "d505" = 233
  dimension "d506" = 2.4
  measures "d504" horizontal distance of origin A0.centre
  measures "d505" vertical distance of origin A0.centre
  measures "d506" diameter of A0
extrude "10 Node register socket (5)''" cut sketch "10 Node register socket sketch (5) (3)" against normal blind 1 bodies 3 in component "Panel upper left"
ref_plane "WorkPlane9" through (0, 0, 5) normal (0, 0, 1) x (1, 0, 0) in component "Panel upper left"
sketch "10 Node register socket sketch (6) (3)" plane through (0, 0, 5) normal (0, 0, 1) x (1, 0, 0) in component "Panel upper left"
  circle A0 centre (115, 125) radius 1.2
  dimension "d511" = 115
  dimension "d512" = 125
  dimension "d513" = 2.4
  measures "d511" horizontal distance of origin A0.centre
  measures "d512" vertical distance of origin A0.centre
  measures "d513" diameter of A0
extrude "10 Node register socket (6)''" cut sketch "10 Node register socket sketch (6) (3)" against normal blind 1 bodies 3 in component "Panel upper left"
ref_plane "WorkPlane10" through (0, 0, 5) normal (0, 0, 1) x (1, 0, 0) in component "Panel upper left"